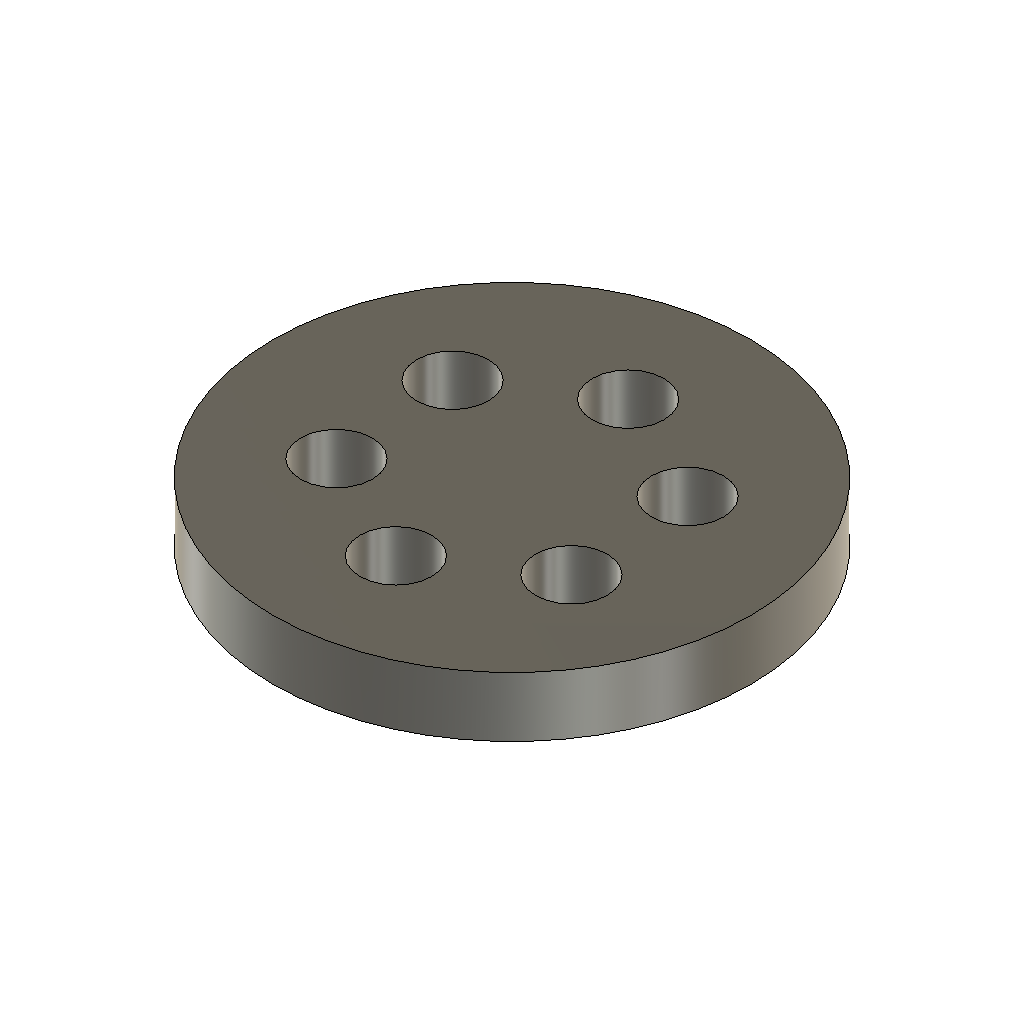
f2sc-test-cpattern (Autodesk Fusion 360 design; units mm, degrees)
part number: 2026-11-27-14-08-20-844
Autodesk Fusion 360 part; units mm, degrees
sketch "Sketch1" plane through (0, 0, 0) normal (0, 0, 1) x (1, 0, 0)
  circle A0 centre (0, 0) radius 20
  dimension "d1" = 40
  constraint coincident A0.centre origin
  measures "d1" diameter of A0
extrude "Extrude1" add sketch "Sketch1" along normal blind 5
hole "Hole1" at (-8.7185, -5.9766, 5) direction (0, 0, -1) diameter 6 depth 6 tip angle 118
pattern_circular "C-Pattern1" count 6 over 360 about axis through (0, 0, 1.75) along (0, 0, 1) of "Hole1"
